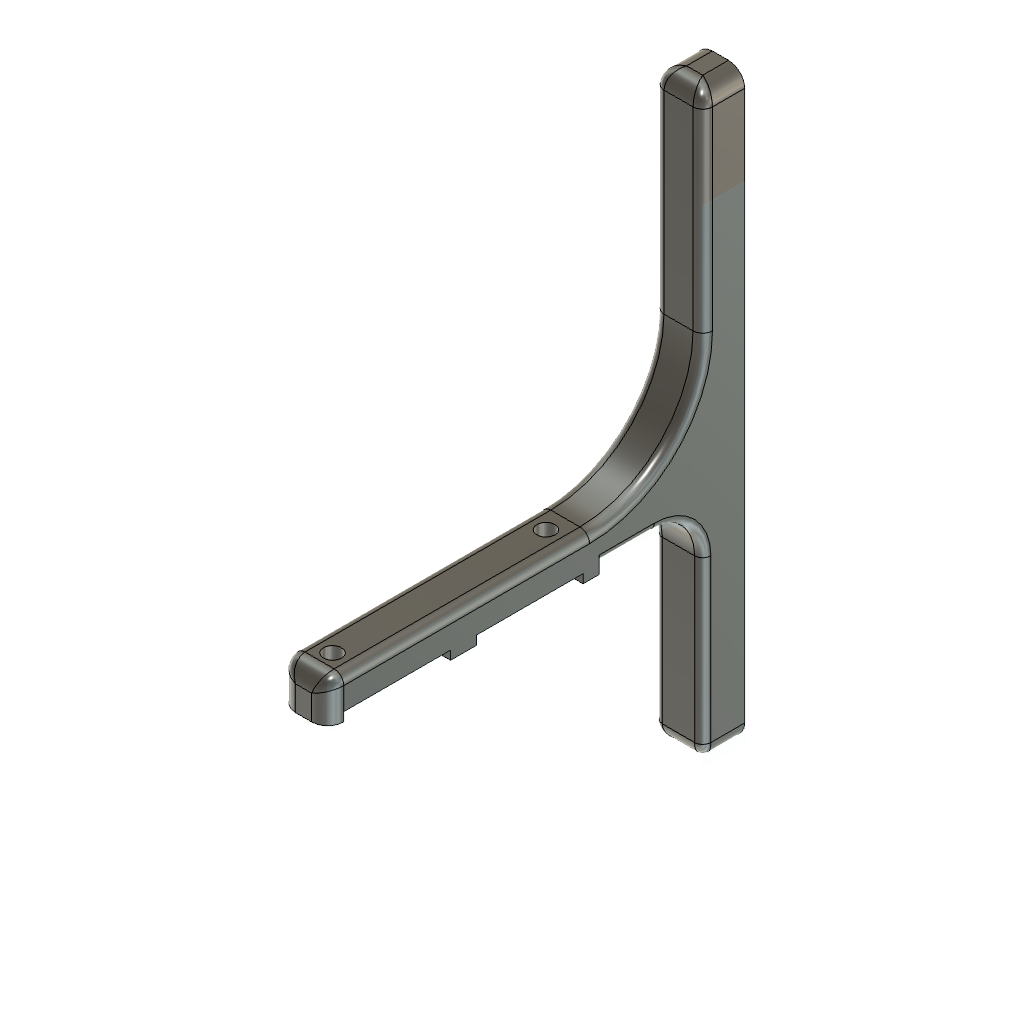
Pi Display Stand (Autodesk Fusion 360 design; units mm, degrees)
Autodesk Fusion 360 part; units mm, degrees
sketch "Sketch1" plane through (0, 0, 0) normal (0, 0, 1) x (1, 0, 0)
  circle A0 centre (0, -33) radius 2
  line L0 (-7.5, 37) -> (7.5, 37)
  line L1 (-7.5, 42) -> (7.5, 42)
  line L2 (-7.5, -42) -> (5.5, -42)
  line L3 (7.5, -42) -> (7.5, 42)
  line L4 (-7.5, -42) -> (7.5, -42)
  line L5 (7.5, 37) -> (7.5, 29)
  line L6 (7.5, 29) -> (-7.5, 29)
  line L7 (-7.5, -29) -> (-7.5, -37)
  line L8 (7.5, 42) -> (-7.5, -42) construction
  line L9 (7.5, -37) -> (7.5, -29)
  line L10 (7.5, 42) -> (-7.5, 42)
  line L11 (5.5, -37) -> (-7.5, -37)
  line L12 (-7.5, 42) -> (7.5, -42) construction
  circle A1 centre (0, 33) radius 2
  line L13 (-7.5, 37) -> (-7.5, 42)
  line L14 (-7.5, -37) -> (7.5, -37)
  line L15 (7.5, -29) -> (-7.5, -29)
  line L16 (7.5, 37) -> (-7.5, 37)
  line L17 (-7.5, -37) -> (-7.5, -42)
  line L18 (-7.5, 29) -> (-7.5, 37)
  line L19 (7.5, 42) -> (7.5, 37)
  line L20 (-7.5, 42) -> (-7.5, -42)
  line L21 (7.5, -4) -> (-7.5, -4)
  line L22 (-7.5, -4) -> (-7.5, 4)
  line L23 (-7.5, 4) -> (7.5, 4)
  line L24 (7.5, 4) -> (7.5, -4)
  line L25 (7.5, -4) -> (-7.5, 4) construction
  line L26 (-7.5, -4) -> (7.5, 4) construction
  dimension "d1" = 15
  dimension "d2" = 84
  dimension "d3" = 5
  dimension "d4" = 5
  dimension "d5" = 8
  dimension "d6" = 8
  dimension "d7" = 4
  dimension "d8" = 4
  dimension "d37" = 8
  constraint horizontal L10
  constraint perpendicular L10 L20
  constraint parallel L4 L10
  constraint parallel L3 L20
  constraint coincident origin L8
  constraint coincident origin L12
  constraint horizontal L2
  constraint horizontal L11
  constraint vertical L17
  constraint horizontal L1
  constraint vertical L19
  constraint horizontal L16
  constraint vertical L13
  constraint horizontal L0
  constraint vertical L5
  constraint horizontal L6
  constraint vertical L18
  constraint horizontal L14
  constraint vertical L9
  constraint horizontal L15
  constraint vertical L7
  constraint horizontal L21
  constraint perpendicular L21 L22
  constraint parallel L21 L23
  constraint parallel L22 L24
  constraint coincident L25 origin
  constraint coincident L26 origin
  measures "d1" distance of L2.start L3.start
  measures "d2" distance of L2.start L1.start
  measures "d3" distance of L2.start L7.end
  measures "d4" distance of L1.start L0.start
  measures "d5" distance of L6.end L0.start
  measures "d6" distance of L7.end L7.start
  measures "d7" diameter of A0
  measures "d8" diameter of A1
  measures "d37" distance of L21.end L22.end
extrude "Extrude1" add sketch "Sketch1" along normal blind 10
extrude "Extrude2" add 1 faces at (-2.5, 42, 3.3333) along direction (0, 1, 0) blind 45
sketch "Sketch2" plane through (7.5, 0, 0) normal (1, 0, 0) x (0, 1, 0)
  line L0 (-42, 0) -> (87, 0)
  line L1 (87, 0) -> (87, 10)
  line L2 (87, 10) -> (-42, 10)
  line L3 (-42, 10) -> (-42, 0)
  line L4 (87, 10) -> (87, 80)
  line L5 (87, 10) -> (157, 10) construction
  line L6 (87, 10) -> (74, 10)
  line L7 (74, 10) -> (74, 80)
  line L8 (87, 80) -> (74, 80)
  line L9 (87, 10) -> (87, 0.8131)
  line L10 (87, 0) -> (85, 0)
  line L11 (87, 0.8131) -> (87, -3.4434)
  line L12 (85, 0) -> (100, 0)
  dimension "d15" = 90
  dimension "d16" = 70
  dimension "d17" = 13
  dimension "d18" = 70
  dimension "d44" = 90
  constraint horizontal L5
  constraint coincident L1.end L2.start
  constraint parallel L2 L6
  constraint parallel L4 L9
  constraint coincident L0.end L1.start
  constraint perpendicular L1 L10
  constraint parallel L9 L11
  constraint parallel L10 L12
  measures "d15" angle of L4 L5
  measures "d16" distance of L1.end L4.end
  measures "d17" distance of L1.end L6.end
  measures "d18" distance of L6.end L7.end
  measures "d44" angle of L7 L8
extrude "Extrude3" add sketch "Sketch2" against normal blind 15
fillet "Fillet1" radius 35 1 edges at (0, 74, 10)
sketch "Sketch3" plane through (7.5, 0, 0) normal (1, 0, 0) x (0, 1, 0)
  line L0 (-42, 0) -> (87, 0)
  line L1 (87, 0) -> (87, 80)
  line L2 (87, 80) -> (74, 80)
  line L3 (74, 80) -> (74, 45)
  arc A0 (39, 10) -> (74, 45) centre (39, 45) ccw
  line L4 (39, 10) -> (-42, 10)
  line L5 (-42, 10) -> (-42, 0)
  line L6 (39, 10) -> (39, 0)
  constraint coincident A0.start L4.start
  constraint coincident L0 L6.end
  constraint perpendicular L0 L6
sketch "Sketch4" plane through (0, 0, 10) normal (0, 0, 1) x (-1, 0, 0)
  line L0 (-7.5, -39) -> (7.5, -39)
  circle A0 centre (0, -33) radius 2.8
  circle A1 centre (0, 33) radius 2.8
  line L1 (7.5, -39) -> (7.5, 42)
  line L2 (7.5, 42) -> (-7.5, 42)
  line L3 (-7.5, 42) -> (-7.5, -39)
  dimension "d31" = 5.6
  dimension "d32" = 5.6
  measures "d31" diameter of A0
  measures "d32" diameter of A1
extrude "Extrude5" cut sketch "Sketch4" against normal blind 6.5 contours A0 | A1
extrude "Extrude6" add sketch "Sketch1" against normal blind 2.75 contours L0 L1 L3 L10 L13 L16 L19 L20 | L3 L20 L21 L22 L23 L24 | L2 L3 L4 L11 L14 L17 L20
extrude "Extrude7" cut sketch "Sketch1" along normal blind 20 contours A0 | A1
sketch "Sketch5" plane through (0, 0, 0) normal (0, 0, -1) x (1, 0, 0)
  line L0 (7.5, -42) -> (-7.5, -42)
  line L1 (-7.5, -42) -> (-7.5, -87)
  line L2 (-7.5, -87) -> (7.5, -87)
  line L3 (7.5, -87) -> (7.5, -42)
  line L4 (-7.5, -87) -> (7.5, -87)
  line L5 (7.5, -87) -> (7.5, -74)
  line L6 (7.5, -74) -> (-7.5, -74)
  line L7 (-7.5, -74) -> (-7.5, -87)
  dimension "d47" = 13
  constraint horizontal L4
  constraint vertical L5
  constraint horizontal L6
  constraint vertical L7
  constraint coincident L1.end L2.start
  measures "d47" distance of L1.end L6.end
extrude "Extrude8" add sketch "Sketch5" along normal blind 70 contours L1 L2 L3 L4 L5 L6 L7
fillet "Fillet8" radius 15 1 edges at (0, 74, 0)
sketch "Sketch6" plane through (7.5, 0, 0) normal (1, 0, 0) x (0, 1, 0)
  line L0 (-37, 0) -> (-4, 0)
  line L1 (-4, 0) -> (-4, -2.75)
  line L2 (-4, -2.75) -> (4, -2.75)
  line L3 (4, -2.75) -> (4, 0)
  line L4 (4, 0) -> (37, 0)
  line L5 (37, 0) -> (37, -2.75)
  line L6 (37, -2.75) -> (42, -2.75)
  line L7 (42, -2.75) -> (42, 0)
  line L8 (42, 0) -> (59, 0)
  arc A0 (74, -15) -> (59, 0) centre (59, -15) ccw
  line L9 (74, -15) -> (74, -70)
  line L10 (74, -70) -> (87, -70)
  line L11 (87, -70) -> (87, 80)
  line L12 (87, 80) -> (74, 80)
  line L13 (74, 80) -> (74, 45)
  arc A1 (39, 10) -> (74, 45) centre (39, 45) ccw
  line L14 (39, 10) -> (-42, 10)
  line L15 (-42, 10) -> (-42, -2.75)
  line L16 (-42, -2.75) -> (-37, -2.75)
  line L17 (-37, -2.75) -> (-37, 0)
extrude "Extrude9" add 1 faces at (2.5, 82.6667, 80) along direction (0, 0, 1) blind 30
fillet "Fillet9" radius 3 6 edges at (7.5, -1.5, 10) (7.5, 63.7487, 20.2513) (7.5, 74, 77.5) (-7.5, 74, 77.5) (-7.5, 63.7487, 20.2513) (-7.5, -1.5, 10)
fillet "Fillet10" radius 5 5 edges at (-7.5, -42, 2.125) (-6.6213, -42, 9.1213) (0, -42, 10) (6.6213, -42, 9.1213) (7.5, -42, 2.125)
fillet "Fillet11" radius 5 5 edges at (-7.5, 82, 110) (-6.6213, 74.8787, 110) (0, 74, 110) (6.6213, 74.8787, 110) (7.5, 82, 110)
fillet "Fillet12" radius 2.5 6 edges at (7.5, 50.5, 0) (7.5, 69.6066, -4.3934) (7.5, 74, -42.5) (-7.5, 50.5, 0) (-7.5, 69.6066, -4.3934) (-7.5, 74, -42.5)
fillet "Fillet13" radius 5 5 edges at (7.5, 81.75, -70) (6.7678, 74.7322, -70) (0, 74, -70) (-6.7678, 74.7322, -70) (-7.5, 81.75, -70)
